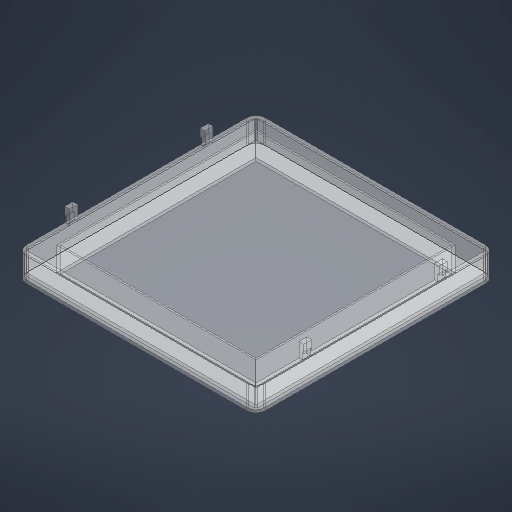
# Autodesk Inventor part: Parte Plástica
Saved by Autodesk Inventor 2027.1 (Build 311270010, 270A)
## iProperties
Created: 2026-07-28
Part Number: Parte Plástica
Material: Genérico
Document SubType Name: Modeling
Designer: enric
Density: 1 g/cm^3
Appearance: Transparente - Claro
Author: enric
Autodesk Inventor part; units mm, degrees
ref_plane "YZ Plane" through (0, 0, 0) normal (1, 0, 0) x (0, 1, 0)
ref_plane "XZ Plane" through (0, 0, 0) normal (0, 1, 0) x (-1, 0, 0)
ref_plane "XY Plane" through (0, 0, 0) normal (0, 0, 1) x (1, 0, 0)
sketch "Esboço1" plane through (0, 0, 0) normal (0, 1, 0) x (-1, 0, 0)
  line L0 (75, -75) -> (-75, -75)
  line L1 (-75, -75) -> (-75, 75)
  line L2 (-75, 75) -> (75, 75)
  line L3 (75, 75) -> (75, -75)
  line L4 (75, -75) -> (-75, 75) construction
  line L5 (-75, -75) -> (75, 75) construction
  point P0 (0, 0)
  dimension "d0" = 150
  dimension "d1" = 150
  constraints: 12 end point, 2 midpoint, 2 parallel, 1 horizontal, 1 perpendicular
  measures "d0" distance of L1.end L2.end
  measures "d1" distance of L0.end L1.end
extrude "Extrusão1" add sketch "Esboço1" against normal blind 15
shell "Casca1" thickness 3 removed faces 1 at (25, 0, 25)
sketch "Esboço2" plane through (-72, -12, 72) normal (0, 1, 0) x (1, 0, 0)
  line L0 (144, 0) -> (0, 0) projected
  line L1 (144, 144) -> (144, 0) projected
  line L2 (0, 144) -> (144, 144) projected
  line L3 (0, 0) -> (0, 144) projected
  line L4 (0, 0) -> (0, 144) projected
  line L5 (144, 0) -> (0, 0) projected
  line L6 (144, 144) -> (144, 0) projected
  line L7 (0, 144) -> (144, 144) projected
  line L8 (134.5, 9.5) -> (9.5, 9.5)
  line L9 (9.5, 9.5) -> (9.5, 134.5)
  line L10 (9.5, 134.5) -> (134.5, 134.5)
  line L11 (134.5, 134.5) -> (134.5, 9.5)
  line L12 (134.5, 9.5) -> (9.5, 134.5) construction
  line L13 (9.5, 9.5) -> (134.5, 134.5) construction
  point P0 (72, 72)
  dimension "d5" = 125
  dimension "d6" = 125
  constraints: 12 end point, 2 midpoint, 2 parallel, 1 horizontal, 1 perpendicular
  measures "d5" distance of L9.end L10.end
  measures "d6" distance of L8.end L9.end
fillet "Arredondamento1" radius 6 4 edges at (-75, -7.5, -75) (75, -7.5, -75) (75, -7.5, 75) (-75, -7.5, 75)
extrude "Extrusão2" add sketch "Esboço2" along normal blind 15 contours L8 L9 L10 L11
shell "Casca2" thickness 1 removed faces 1 at (-20.8333, 3, 20.8333)
ref_plane "Plano de trabalho1" through (0, 0, 0) normal (0, 1, 0) x (1, 0, 0)
sketch "Esboço3" plane through (0, 0, 0) normal (0, 1, 0) x (1, 0, 0)
  line L0 (-75, 69) -> (-75, -69) projected
  line L1 (-75, 42.5) -> (-75, -42.5)
  line L2 (-75, -40) -> (-75, -45)
  line L3 (-72, -72) -> (-72, 72) projected
  line L4 (-75, -40) -> (-72, -40)
  line L5 (-72, -45) -> (-75, -45)
  line L6 (-74, 69) -> (-74, -69) projected
  line L7 (-75, 45) -> (-75, 40)
  line L8 (-75, 45) -> (-72, 45)
  line L9 (-72, 40) -> (-75, 40)
  line L10 (75, -69) -> (75, 69) projected
  line L11 (72, 72) -> (72, -72) projected
  line L12 (75, 42.5) -> (75, -42.5) construction
  line L13 (75, -40) -> (75, -45)
  line L14 (75, 40) -> (75, 45)
  line L15 (75, 45) -> (72, 45)
  line L16 (72, 40) -> (75, 40)
  line L17 (75, -40) -> (72, -40)
  line L18 (72, -45) -> (75, -45)
  line L19 (74, -69) -> (74, 69) projected
  point P0 (0, 0)
  point P1 (-75, 0)
  point P2 (75, 0)
  point P3 (74, 40)
  point P4 (74, 45)
  point P5 (74, -45)
  point P6 (74, -40)
  point P7 (-74, -40)
  point P8 (-74, -45)
  point P9 (-74, 40)
  point P10 (-74, 45)
  dimension "d12" = 85
  dimension "d13" = 5
  dimension "d15" = 5
  dimension "d16" = 85
  dimension "d17" = 5
  dimension "d18" = 5
  constraints: 28 end point, 14 point on line, 8 midpoint, 8 perpendicular
  measures "d12" distance of L1.start L1.end
  measures "d13" distance of L2.start L2.end
  measures "d15" distance of L7.start L7.end
  measures "d16" distance of L12.start L12.end
  measures "d17" distance of L13.start L13.end
  measures "d18" distance of L14.start L14.end
extrude "Extrusão3" add sketch "Esboço3" along normal blind 9 contours L8 L3 L9 L6 | L4 L3 L5 L6 | L18 L11 L17 L19 | L16 L11 L15 L19
sketch "Esboço4" plane through (-74, 0, -40) normal (-1, 0, 0) x (0, 0, 1)
  line L0 (-5, 9) -> (0, 9) projected
  line L1 (-5, 0) -> (-5, 9) projected
  line L2 (0, 0) -> (0, 9) projected
  line L3 (80, 9) -> (85, 9) projected
  line L4 (80, 0) -> (80, 9) projected
  line L5 (85, 0) -> (85, 9) projected
  line L6 (-5, 9) -> (0, 9)
  line L7 (0, 9) -> (0, 4)
  line L8 (0, 4) -> (-5, 4)
  line L9 (-5, 4) -> (-5, 9)
  line L10 (80, 9) -> (85, 9)
  line L11 (85, 9) -> (85, 4)
  line L12 (85, 4) -> (80, 4)
  line L13 (80, 4) -> (80, 9)
  point P0 (40, 0)
  dimension "d21" = 5
  dimension "d22" = 5
  dimension "d23" = 5
  dimension "d24" = 5
  constraints: 16 end point, 4 parallel, 2 horizontal, 2 perpendicular
  measures "d21" distance of L7.end L8.end
  measures "d22" distance of L6.end L7.end
  measures "d23" distance of L11.end L12.end
  measures "d24" distance of L10.end L11.end
extrude "Extrusão4" add sketch "Esboço4" along normal blind 1
sketch "Esboço5" plane through (74, 0, 40) normal (1, 0, 0) x (0, 0, -1)
  line L0 (-5, 0) -> (-5, 9) projected
  line L1 (-5, 9) -> (0, 9) projected
  line L2 (0, 0) -> (0, 9) projected
  line L3 (80, 0) -> (80, 9) projected
  line L4 (80, 9) -> (85, 9) projected
  line L5 (85, 0) -> (85, 9) projected
  line L6 (-5, 9) -> (0, 9)
  line L7 (0, 9) -> (0, 4)
  line L8 (0, 4) -> (-5, 4)
  line L9 (-5, 4) -> (-5, 9)
  line L10 (80, 9) -> (85, 9)
  line L11 (85, 9) -> (85, 4)
  line L12 (85, 4) -> (80, 4)
  line L13 (80, 4) -> (80, 9)
  point P0 (40, 0)
  dimension "d27" = 5
  dimension "d28" = 5
  dimension "d29" = 5
  dimension "d30" = 5
  constraints: 16 end point, 4 parallel, 2 horizontal, 2 perpendicular
  measures "d27" distance of L7.end L8.end
  measures "d28" distance of L6.end L7.end
  measures "d29" distance of L11.end L12.end
  measures "d30" distance of L10.end L11.end
extrude "Extrusão5" add sketch "Esboço5" along normal blind 1
